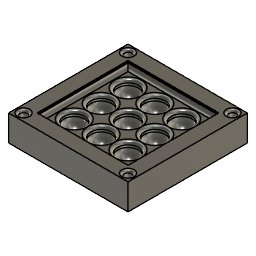
RUN 6 MOLD (Autodesk Fusion 360 design; units mm, degrees)
Autodesk Fusion 360 part; units mm, degrees
sketch "Sketch1" plane through (0, 0, 0) normal (0, 0, 1) x (1, 0, 0)
  line L0 (15, 15) -> (-15, 15)
  line L1 (-15, 15) -> (-15, -15)
  line L2 (-15, -15) -> (15, -15)
  line L3 (15, -15) -> (15, 15)
  line L4 (15, 15) -> (-15, -15) construction
  line L5 (-15, 15) -> (15, -15) construction
  circle A0 centre (0, 0) radius 3.5
  circle A1 centre (-9, -9) radius 3.5
  circle A2 centre (0, -9) radius 3.5
  circle A3 centre (9, -9) radius 3.5
  circle A4 centre (-9, 0) radius 3.5
  circle A5 centre (9, 0) radius 3.5
  circle A6 centre (-9, 9) radius 3.5
  circle A7 centre (0, 9) radius 3.5
  circle A8 centre (9, 9) radius 3.5
  line L6 (20, -20) -> (20, 20)
  line L7 (20, 20) -> (-20, 20)
  line L8 (-20, 20) -> (-20, -20)
  line L9 (-20, -20) -> (20, -20)
  dimension "d1" = 30
  dimension "d2" = 30
  dimension "d3" = 7
  dimension "d6" = 9
  dimension "d7" = 9
  dimension "d8" = 5
  constraint horizontal L0
  constraint perpendicular L0 L1
  constraint parallel L0 L2
  constraint parallel L1 L3
  constraint coincident L4 A0.centre
  constraint coincident L5 A0.centre
  constraint coincident A0.centre origin
  measures "d1" distance of L1.end L2.end
  measures "d2" distance of L0.end L1.end
  measures "d3" diameter of A0
extrude "Extrude1" add sketch "Sketch1" against normal blind 7 contours L0 L1 L2 L3 | A0 | A1 | A2 | A3 | A4 | A5 | A6 | A7 | A8
extrude "Extrude2" add sketch "Sketch1" along normal blind 1.75 and the other way blind 7 contours L6 L7 L8 L9
extrude "Extrude3" cut sketch "Sketch1" against normal blind 5.25 contours A0 | A1 | A2 | A3 | A4 | A5 | A6 | A7 | A8
fillet "Fillet1" radius 3.5 9 edges at (-12.2631, 10.2657, -5.25) (-12.2631, 1.2657, -5.25) (-12.2631, -7.7343, -5.25) (-3.2631, -7.7343, -5.25) (5.7369, -7.7343, -5.25) (5.7369, 1.2657, -5.25) (5.7369, 10.2657, -5.25) (-3.2631, 10.2657, -5.25) (-3.2631, 1.2657, -5.25)
fillet "Fillet2" radius 1.25 4 edges at (-15, 0, 0) (0, -15, 0) (15, 0, 0) (0, 15, 0)
fillet "Fillet3" radius 1 9 edges at (-3.2631, 1.2657, 0) (5.7369, 1.2657, 0) (5.7369, -7.7343, 0) (-3.2631, -7.7343, 0) (-12.2631, -7.7343, 0) (-12.2631, 1.2657, 0) (-12.2631, 10.2657, 0) (-3.2631, 10.2657, 0) (5.7369, 10.2657, 0)
sketch "Sketch2" plane through (0, 0, 1.75) normal (0, 0, 1) x (-1, 0, 0)
  line L0 (-15, -15) -> (-15, 15)
  line L1 (-15, 15) -> (15, 15)
  line L2 (15, 15) -> (15, -15)
  line L3 (15, -15) -> (-15, -15)
  line L4 (20, 20) -> (-20, 20)
  line L5 (-20, 20) -> (-20, -20)
  line L6 (-20, -20) -> (20, -20)
  line L7 (20, -20) -> (20, 20)
  line L8 (20, -20) -> (15, -15)
  line L9 (-15, -15) -> (-20, -20)
  line L10 (-15, 15) -> (-20, 20)
  line L11 (15, 15) -> (20, 20)
  circle A0 centre (-17.5, 17.5) radius 1.25
  circle A1 centre (17.5, 17.5) radius 1.25
  circle A2 centre (17.5, -17.5) radius 1.25
  circle A3 centre (-17.5, -17.5) radius 1.25
  dimension "d23" = 2.5
  dimension "d24" = 2.5
  dimension "d25" = 2.5
  dimension "d26" = 2.5
  constraint coincident L6.end L7.start
  constraint coincident L2.end L3.start
  constraint coincident L0.start L3.end
  constraint coincident L5.end L6.start
  constraint coincident L0.end L1.start
  constraint coincident L4.end L5.start
  constraint coincident L1.end L2.start
  constraint coincident L4.start L7.end
  constraint midpoint L10 A0.centre
  constraint midpoint L11 A1.centre
  constraint midpoint L8 A2.centre
  constraint midpoint L9 A3.centre
  measures "d23" diameter of A0
  measures "d24" diameter of A1
  measures "d25" diameter of A2
  measures "d26" diameter of A3
extrude "Extrude4" cut sketch "Sketch2" against normal blind 11 contours L9 A3 | L9 A3 | L10 A0 | L10 A0 | L8 A2 | L8 A2 | L11 A1 | L11 A1
fillet "Fillet4" radius 0.8 4 edges at (18.6654, -17.952, 1.75) (18.6654, 17.048, 1.75) (-16.3346, 17.048, 1.75) (-16.3346, -17.952, 1.75)
fillet "Fillet5" radius 0.2 4 edges at (15, 0, 1.75) (0, -15, 1.75) (0, 15, 1.75) (-15, 0, 1.75)
sketch "Sketch3" plane through (0, 0, -7) normal (0, 0, -1) x (1, 0, 0)
  circle A0 centre (-17.5, 17.5) radius 1.25
  circle A1 centre (17.5, 17.5) radius 1.25
  circle A2 centre (-17.5, -17.5) radius 1.25
  circle A3 centre (17.5, -17.5) radius 1.25
  line L0 (20, 20) -> (-20, 20)
  line L1 (-20, 20) -> (-20, -20)
  line L2 (-20, -20) -> (20, -20)
  line L3 (20, -20) -> (20, 20)
  line L4 (1, 1) -> (-1, 1)
  line L5 (-1, 1) -> (-1, -1)
  line L6 (-1, -1) -> (1, -1)
  line L7 (1, -1) -> (1, 1)
  line L8 (1, 1) -> (-1, -1) construction
  line L9 (-1, 1) -> (1, -1) construction
  line L10 (1, -7) -> (-1, -7)
  line L11 (-1, -7) -> (-1, -9)
  line L12 (-1, -9) -> (1, -9)
  line L13 (1, -9) -> (1, -7)
  line L14 (1, -3) -> (-1, -3)
  line L15 (-1, -3) -> (-1, -5)
  line L16 (-1, -5) -> (1, -5)
  line L17 (1, -5) -> (1, -3)
  line L18 (1, 5) -> (-1, 5)
  line L19 (-1, 5) -> (-1, 3)
  line L20 (-1, 3) -> (1, 3)
  line L21 (1, 3) -> (1, 5)
  line L22 (1, 9) -> (-1, 9)
  line L23 (-1, 9) -> (-1, 7)
  line L24 (-1, 7) -> (1, 7)
  line L25 (1, 7) -> (1, 9)
  line L26 (1, 13) -> (-1, 13)
  line L27 (-1, 13) -> (-1, 11)
  line L28 (-1, 11) -> (1, 11)
  line L29 (1, 11) -> (1, 13)
  dimension "d33" = 2
  dimension "d34" = 2
  dimension "d37" = 0
  dimension "d38" = 12
  constraint horizontal L4
  constraint perpendicular L4 L5
  constraint parallel L4 L6
  constraint parallel L5 L7
  constraint coincident L8 origin
  constraint coincident L9 origin
  measures "d33" distance of L5.end L6.end
  measures "d34" distance of L4.end L5.end
extrude "Extrude5" cut sketch "Sketch3" against normal blind 1 contours L4 L5 L6 L7 | L10 L11 L12 L13 | L14 L15 L16 L17 | L18 L19 L20 L21 | L22 L23 L24 L25 | L26 L27 L28 L29
